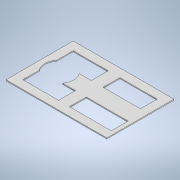
# Autodesk Inventor part: 雪弗板（0.3×20×30cm）每组1份
Saved by Autodesk Inventor 2021 (Build 250183000, 183)
## iProperties
Created: 2024-05-07
Part Number: 雪弗板（0.3×20×30cm）每组1份
Material: 常规
Document SubType Name: Modeling
Designer: PC
Density: 1 g/cm^3
Appearance: 默认
Author: PC
Autodesk Inventor part; units mm, degrees
ref_plane "YZ Plane" through (0, 0, 0) normal (1, 0, 0) x (0, 1, 0)
ref_plane "XZ Plane" through (0, 0, 0) normal (0, 1, 0) x (-1, 0, 0)
ref_plane "XY Plane" through (0, 0, 0) normal (0, 0, 1) x (1, 0, 0)
sketch "草图1" plane through (0, 0, 0) normal (0, 1, 0) x (-1, 0, 0)
  line L0 (150, 100) -> (-150, 100)
  line L1 (-150, 100) -> (-150, -100)
  line L2 (-150, -100) -> (150, -100)
  line L3 (150, -100) -> (150, 100)
  line L4 (150, 100) -> (-150, -100) construction
  line L5 (-150, 100) -> (150, -100) construction
  point P0 (0, 0)
  dimension "d0" = 300
  dimension "d1" = 200
  constraints: 12 end point, 2 midpoint, 2 parallel, 1 horizontal, 1 perpendicular
  measures "d0" distance of L2.end L1.end
  measures "d1" distance of L1.end L0.end
extrude "拉伸1" add sketch "草图1" along normal blind 3
sketch "草图2" plane through (0, 3, 0) normal (0, 1, 0) x (1, 0, 0)
  line L0 (-125, 75) -> (-20.8739, 75)
  line L1 (-20.8739, 75) -> (-20.8739, 25)
  line L2 (-20.8739, 25) -> (-125, 25)
  line L3 (-125, 25) -> (-125, 75)
  line L4 (14.1321, 75) -> (125, 75)
  line L5 (125, 75) -> (125, 25)
  line L6 (125, 25) -> (14.1321, 25)
  line L7 (14.1321, 25) -> (14.1321, 75)
  line L8 (150, 100) -> (-150, 100) projected
  line L9 (150, -100) -> (150, 100) projected
  line L10 (-150, 100) -> (-150, -100) projected
  line L11 (-125, -25) -> (-18.5681, -25)
  line L12 (-18.5681, -25) -> (-18.5681, -75)
  line L13 (-18.5681, -75) -> (-125, -75)
  line L14 (-125, -75) -> (-125, -25)
  line L15 (14.1321, -25) -> (138.4992, -25)
  line L16 (138.4992, -25) -> (138.4992, -75)
  line L17 (138.4992, -75) -> (14.1321, -75)
  line L18 (14.1321, -75) -> (14.1321, -25)
  line L19 (-150, -100) -> (150, -100) projected
  line L20 (-150, 0) -> (150, 0)
  circle A0 centre (-91.3352, 0) radius 42.7822
  point P0 (0, 0)
  point P1 (-125, 26.4008)
  point P2 (-125, -26.4008)
  point P3 (-56.6176, -25)
  point P4 (-56.6176, 25)
  dimension "d4" = 25
  dimension "d5" = 25
  dimension "d6" = 25
  dimension "d7" = 25
  dimension "d8" = 25
  dimension "d9" = 25
  dimension "d10" = 25
  dimension "d11" = 25
  dimension "d12" = 25
  constraints: 34 end point, 8 parallel, 4 horizontal, 4 perpendicular, 3 point on line, 2 midpoint, 1 centre point
  measures "d4" distance between parallel lines of L8 L0
  measures "d5" distance between parallel lines of L9 L5
  measures "d6" distance between parallel lines of L10 L3
  measures "d7" distance between parallel lines of L19 L13
  measures "d8" distance between parallel lines of L10 L14
  measures "d9" distance between parallel lines of L20 L11
  measures "d10" distance between parallel lines of L20 L2
  measures "d11" distance between parallel lines of L20 L6
  measures "d12" distance between parallel lines of L8 L4
extrude "拉伸2" cut sketch "草图2" against normal blind 3 contours L0 L1 L2 A0 L3 | A0 L2 L3 | L3 L2 A0 L20 | L20 A0 L11 L14 | A0 L11 L12 L13 L14 | L14 L11 A0 | L4 L5 L6 L7 | L15 L16 L17 L18
